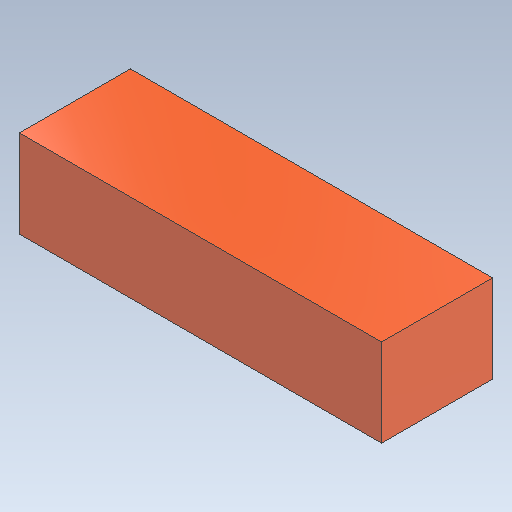
# Autodesk Inventor part: Tattu 850mAh 2S
Saved by Autodesk Inventor 2026.4 (Build 304435000, 435)
## iProperties
Created: 2026-11-13
Part Number: Tattu 850mAh 2S
Material: Generisch
Document SubType Name: Modeling
Designer: weira
Density: 1 g/cm^3
Appearance: Vorgabe
Author: weira
Autodesk Inventor part; units mm, degrees
ref_plane "YZ Plane" through (0, 0, 0) normal (1, 0, 0) x (0, 1, 0)
ref_plane "XZ Plane" through (0, 0, 0) normal (0, 1, 0) x (-1, 0, 0)
ref_plane "XY Plane" through (0, 0, 0) normal (0, 0, 1) x (1, 0, 0)
sketch "Skizze1" plane through (0, 0, 0) normal (0, 0, 1) x (1, 0, 0)
  line L0 (-31, 9.5) -> (31, 9.5)
  line L1 (31, 9.5) -> (31, -9.5)
  line L2 (31, -9.5) -> (-31, -9.5)
  line L3 (-31, -9.5) -> (-31, 9.5)
  line L4 (-31, 9.5) -> (31, -9.5) construction
  line L5 (31, 9.5) -> (-31, -9.5) construction
  point P0 (0, 0)
  dimension "d0" = 19
  dimension "d1" = 62
  constraints: 12 end point, 2 midpoint, 2 parallel, 1 horizontal, 1 perpendicular
  measures "d0" distance of L0.end L1.end
  measures "d1" distance of L0.start L0.end
extrude "Extrusion1" add sketch "Skizze1" along normal blind 15
